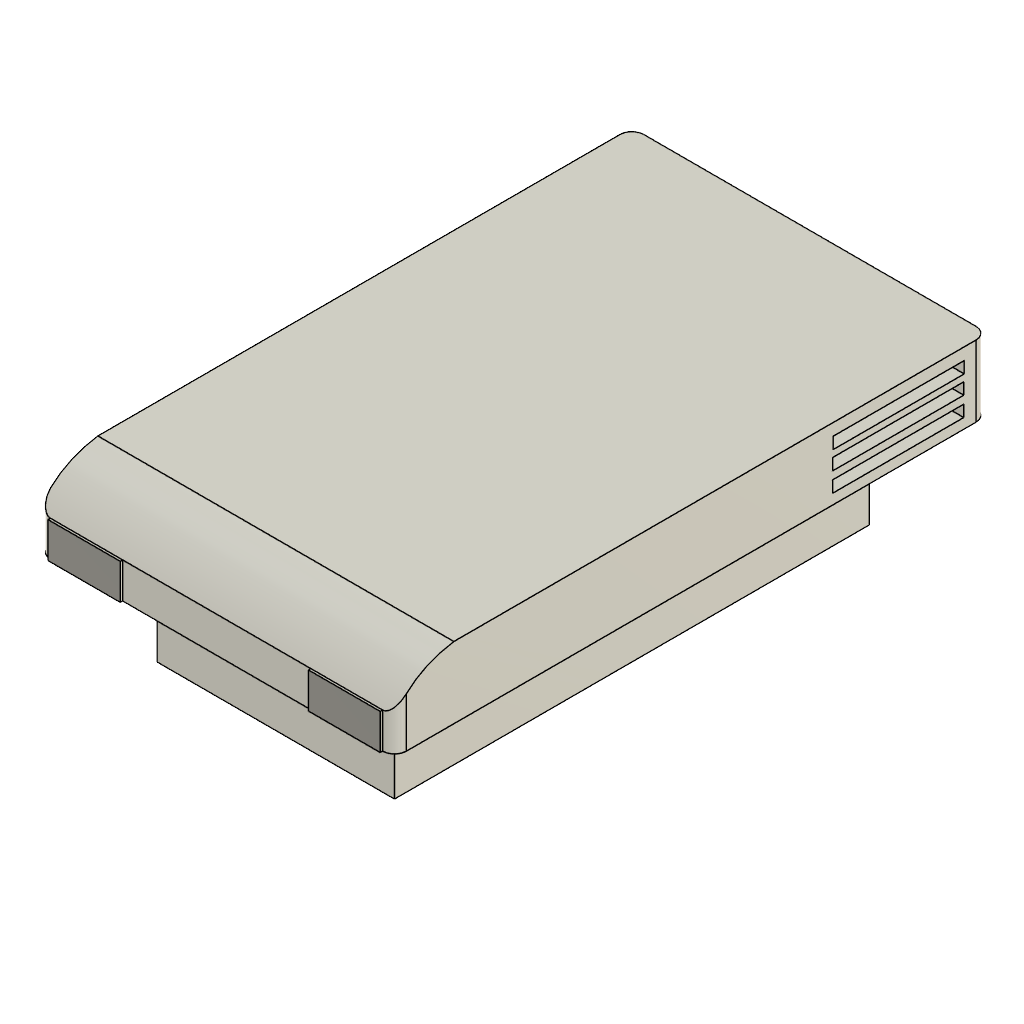
chassis_robot_desherbeur (Autodesk Fusion 360 design; units mm, degrees)
part number: 2026-11-26-20-07-29-653
Autodesk Fusion 360 part; units mm, degrees
sketch "Esquisse1" plane through (0, 0, 0) normal (0, 0, 1) x (1, 0, 0)
  line L0 (50, -100) -> (-50, -100)
  line L1 (-50, -100) -> (-50, 100)
  line L2 (-50, 100) -> (50, 100)
  line L3 (50, 100) -> (50, -100)
  line L4 (50, -100) -> (-50, 100) construction
  line L5 (-50, -100) -> (50, 100) construction
  dimension "d1" = 100
  dimension "d2" = 200
  constraint horizontal L0
  constraint perpendicular L0 L1
  constraint parallel L0 L2
  constraint parallel L1 L3
  constraint coincident L4 origin
  constraint coincident L5 origin
  measures "d1" distance of L1.end L2.end
  measures "d2" distance of L0.end L1.end
extrude "Extrusion1" add sketch "Esquisse1" along normal blind 40
shell "Coque1" thickness 2 removed faces 1 at (16.6667, -33.3333, 40)
ref_plane "Plan de construction1" through (0, 0, 40) normal (0, 0, 1) x (1, 0, 0)
sketch "Esquisse2" plane through (0, 0, 40) normal (0, 0, 1) x (1, 0, 0)
  line L0 (75, -125) -> (-75, -125)
  line L1 (-75, -125) -> (-75, 125)
  line L2 (-75, 125) -> (75, 125)
  line L3 (75, 125) -> (75, -125)
  line L4 (75, -125) -> (-75, 125) construction
  line L5 (-75, -125) -> (75, 125) construction
  dimension "d8" = 150
  dimension "d9" = 250
  constraint horizontal L0
  constraint perpendicular L0 L1
  constraint parallel L0 L2
  constraint parallel L1 L3
  constraint coincident L4 origin
  constraint coincident L5 origin
extrude "Extrusion2" add sketch "Esquisse2" along normal blind 30
sketch "Esquisse3" plane through (75, 0, 0) normal (1, 0, 0) x (0, 1, 0)
  line L0 (-125, 40) -> (125, 40)
  line L1 (125, 40) -> (125, 70)
  line L2 (125, 70) -> (-125, 70)
  line L3 (-125, 70) -> (-125, 40)
  line L4 (59.7923, 65) -> (115, 65)
  line L5 (115, 65) -> (115, 60.1222)
  line L6 (115, 60.1222) -> (59.7923, 60.1222)
  line L7 (59.7923, 60.1222) -> (59.7923, 65)
  line L8 (114.8036, 52.4629) -> (59.5959, 52.4629)
  line L9 (59.5959, 52.4629) -> (59.5959, 57.3407)
  line L10 (59.5959, 57.3407) -> (114.8036, 57.3407)
  line L11 (114.8036, 57.3407) -> (114.8036, 52.4629)
  line L12 (114.8036, 44.3126) -> (59.5959, 44.3126)
  line L13 (59.5959, 44.3126) -> (59.5959, 49.1904)
  line L14 (59.5959, 49.1904) -> (114.8036, 49.1904)
  line L15 (114.8036, 49.1904) -> (114.8036, 44.3126)
  constraint horizontal L4
  constraint vertical L5
  constraint horizontal L6
  constraint vertical L7
  constraint horizontal L10
  constraint vertical L11
  constraint horizontal L8
  constraint vertical L9
  constraint horizontal L14
  constraint vertical L15
  constraint horizontal L12
  constraint vertical L13
extrude "Extrusion6" cut sketch "Esquisse3" against normal blind 250 contours L4 L5 L6 L7 | L8 L9 L10 L11 | L12 L13 L14 L15
sketch "Esquisse4" plane through (0, 0, 0) normal (1, 0, 0) x (0, 1, 0)
  line L0 (125, 70) -> (-125, 70)
  line L1 (-125, 70) -> (-125, 40)
  line L2 (-125, 40) -> (125, 40)
  spline S0 degree 5 poles (-74.0098, 70) (-76.3613, 70.261) (-81.0281, 70.6829) (-87.9196, 71.0155) (-96.8756, 70.8171) (-107.4933, 68.9754) (-115.2346, 65.424) (-120.4044, 61.0043) (-123.5228, 57.1525) (-125, 55) knots 0 0 0 0 0 0 0.2 0.4 0.6 0.8 1 1 1 1 1 1
  line L3 (-121.5687, 60) -> (-128.4313, 50)
  line L4 (-74.0098, 70) -> (-125, 70)
  line L5 (-125, 55) -> (-125, 70)
  constraint midpoint S0.end L3
  constraint coincident L0.end L1.start
  constraint perpendicular L1 L4
  constraint perpendicular L4 L5
  constraint midpoint L1 S0.end
extrude "Extrusion7" cut sketch "Esquisse4" along normal mid plane 400 contours L0 L1 S0 L4 L5
fillet "Congé1" radius 5 1 edges at (75, -125, 47.5)
fillet "Congé1" radius 5 1 edges at (-75, -125, 47.5)
fillet "Congé1" radius 5 2 edges at (75, 125, 55) (-75, 125, 55)
sketch "Esquisse5" plane through (0, 0, 0) normal (0, 0, -1) x (1, 0, 0)
  line L0 (-50, -100) -> (50, -100)
  line L1 (50, -100) -> (50, 100)
  line L2 (50, 100) -> (-50, 100)
  line L3 (-50, 100) -> (-50, -100)
  line L4 (0, 100) -> (0, 60) construction
  circle A0 centre (0, 60) radius 5
  dimension "d32" = 40
  dimension "d33" = 10
  constraint midpoint L2 L4.start
  constraint perpendicular L2 L4
  constraint coincident L4.end A0.centre
  measures "d32" distance of L4.start L4.end
  measures "d33" diameter of A0
extrude "Extrusion8" add sketch "Esquisse5" along normal blind 10 contours A0
sketch "Esquisse7" plane through (0, -125, 0) normal (0, -1, 0) x (1, 0, 0)
  line L0 (-70, 55) -> (-70, 40)
  line L1 (-70, 40) -> (70, 40)
  line L2 (70, 40) -> (70, 55)
  line L3 (70, 55) -> (-70, 55)
  line L4 (-39.5034, 55) -> (-39.5034, 40)
  line L5 (39.7668, 55) -> (39.7668, 40)
  constraint coincident L3 L4.start
  constraint coincident L1 L4.end
  constraint perpendicular L1 L4
  constraint coincident L3 L5.start
  constraint coincident L1 L5.end
  constraint perpendicular L1 L5
extrude "Extrusion9" add sketch "Esquisse7" along normal blind 1 contours L0 L1 L3 L4 | L1 L2 L3 L5
